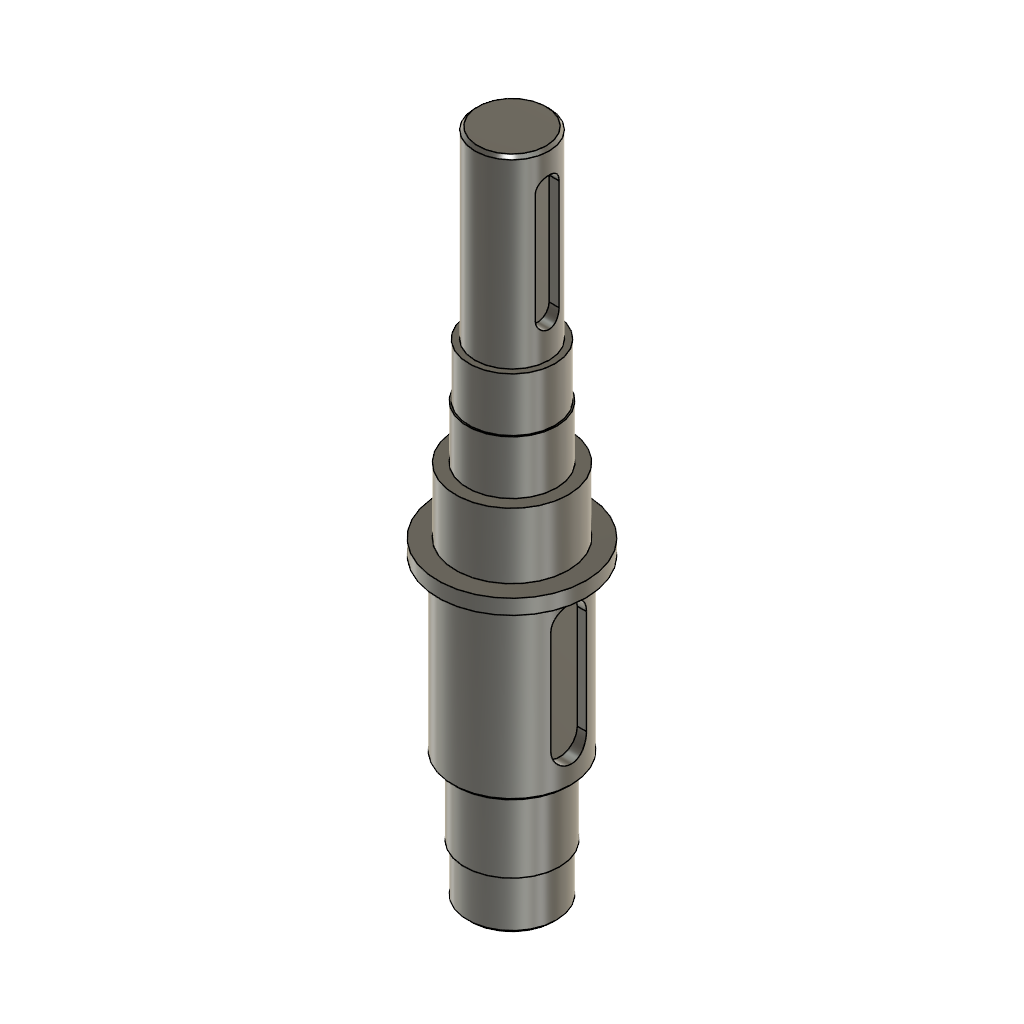
arbre (Autodesk Fusion 360 design; units mm, degrees)
part number: 2026-10-23-14-36-01-501
Autodesk Fusion 360 part; units mm, degrees
sketch "Esquisse1" plane through (0, 0, 0) normal (0, 1, 0) x (1, 0, 0)
  line L0 (20.5, -20) -> (33, -20)
  line L1 (33, -20) -> (33, 42)
  line L2 (33, 42) -> (35, 42)
  line L3 (35, 42) -> (35, 60)
  line L4 (35, 60) -> (35.5, 60)
  line L5 (35.5, 60) -> (35.5, 78)
  line L6 (35.5, 78) -> (39.5, 78)
  line L7 (39.5, 78) -> (39.5, 100)
  line L8 (39.5, 100) -> (45.5, 100)
  line L9 (45.5, 105) -> (40.5, 105)
  line L10 (45.5, 100) -> (45.5, 105)
  line L11 (40.5, 105) -> (40.5, 163)
  line L12 (40.5, 163) -> (36.5, 163)
  line L13 (36.5, 163) -> (36.5, 188)
  line L14 (36.5, 188) -> (35.5, 188)
  line L15 (35.5, 188) -> (35.5, 205)
  line L16 (35.5, 205) -> (20.5, 205)
  line L17 (20.5, -20) -> (20.5, 205)
  dimension "d1" = 12.5
  dimension "d2" = 62
  dimension "d3" = 80
  dimension "d4" = 18
  dimension "d5" = 225
  dimension "d6" = 17
  dimension "d7" = 58
  dimension "d8" = 100
  dimension "d9" = 5
  dimension "d10" = 14.5
  dimension "d11" = 15
  dimension "d12" = 19
  dimension "d13" = 25
  dimension "d14" = 20
  dimension "d15" = 16
  dimension "d16" = 15
  constraint horizontal L0
  constraint perpendicular L0 L1
  constraint perpendicular L1 L2
  constraint perpendicular L2 L3
  constraint perpendicular L3 L4
  constraint perpendicular L4 L5
  constraint perpendicular L3 L6
  constraint perpendicular L6 L7
  constraint perpendicular L7 L8
  constraint perpendicular L9 L10
  constraint perpendicular L9 L11
  constraint perpendicular L11 L12
  constraint perpendicular L12 L13
  constraint perpendicular L13 L14
  constraint perpendicular L14 L15
  constraint perpendicular L15 L16
  constraint perpendicular L16 L17
  measures "d1" distance of L0.start L0.end
  measures "d2" distance of L0.end L1.end
  measures "d3" distance of L0 L4
  measures "d4" distance of L4 L6
  measures "d5" distance of L0 L16
  measures "d6" distance of L14 L16
  measures "d7" distance of L9 L12
  measures "d8" distance of L9 L16
  measures "d9" distance of L8.end L9.start
  measures "d10" distance of L3 L17
  measures "d11" distance of L5 L17
  measures "d12" distance of L7 L17
  measures "d13" distance of L10 L17
  measures "d14" distance of L11 L17
  measures "d15" distance of L13 L17
  measures "d16" distance of L15 L17
revolve "Révolution3" add sketch "Esquisse1" angle 360 about axis through (20.5, 0, 20) along (0, 0, -1)
ref_plane "Plan de construction7" through (33, 0, -9.776) normal (1, 0, 0) x (0, -1, 0)
sketch "Esquisse8" plane through (33, 0, 0) normal (1, 0, 0) x (0, 1, 0)
  line L0 (0, 20) -> (0, 8) construction
  line L1 (-4, 8) -> (-4, -29)
  arc A0 (-4, -29) -> (4, -29) centre (0, -29) ccw
  line L2 (4, -29) -> (4, 8)
  arc A1 (4, 8) -> (-4, 8) centre (0, 8) ccw
  line L3 (0, 8) -> (0, -29) construction
  dimension "d51" = 12
  dimension "d52" = 37
  dimension "d53" = 8
  constraint vertical L0
  constraint tangent L1 A0
  constraint tangent A0 L2
  constraint parallel L1 L2
  constraint tangent L2 A1
  constraint tangent L1 A1
  constraint parallel L0 L3
  constraint coincident L0.end A1.centre
  measures "d51" distance of L0.start L0.end
  measures "d52" distance of L0.end A0.centre
  measures "d53" diameter of A0
extrude "Extrusion3" cut sketch "Esquisse8" against normal blind 4
ref_plane "Plan de construction8" through (40.5, 0, -143.2037) normal (1, 0, 0) x (0, -1, 0)
sketch "Esquisse9" plane through (40.5, 0, 0) normal (1, 0, 0) x (0, 1, 0)
  line L0 (0, -105) -> (0, -115) construction
  line L1 (-6, -115) -> (-6, -150)
  arc A0 (-6, -150) -> (6, -150) centre (0, -150) ccw
  line L2 (6, -150) -> (6, -115)
  arc A1 (6, -115) -> (-6, -115) centre (0, -115) ccw
  line L3 (0, -115) -> (0, -150) construction
  dimension "d58" = 10
  dimension "d59" = 12
  constraint vertical L0
  constraint tangent L1 A0
  constraint tangent A0 L2
  constraint parallel L1 L2
  constraint tangent L2 A1
  constraint tangent L1 A1
  constraint parallel L0 L3
  constraint coincident L0.end A1.centre
  measures "d58" distance of L0.start L0.end
  measures "d59" diameter of A0
extrude "Extrusion4" cut sketch "Esquisse9" against normal blind 4
chamfer "Chanfrein1" distance 1 angle 45 1 edges at (8.8459, -4.5202, 20) tangent chain off
chamfer "Chanfrein2" distance 1 angle 45 1 edges at (6.5151, -5.4242, -205) tangent chain off
chamfer "Chanfrein3" distance 1 angle 45 1 edges at (1.8535, -7.2323, -163) tangent chain off
